Autodesk Fusion 360 part; units mm, degrees
(part 7 of 7)
component "rear deck crossmember" placed x (-1, 0, 0) y (0, 0, 1) z (0, 1, 0) at (-188, -315, 113)
component "front deck crossmember" placed x (-1, 0, 0) y (0, 0, 1) z (0, 1, 0) at (176, -315, 113)
component "left electronics deck" placed x (1, 0, 0) y (0, 1, 0) z (0, 0, 1) at (-5.5, 149, 122)
component "right electronics deck" placed x (1, 0, 0) y (0, 1, 0) z (0, 0, 1) at (-5.5, -147.5, 122)
component "fore electronics deck bridge" placed x (1, 0, 0) y (0, 1, 0) z (0, 0, 1) at (110.5, 1.5, 122)
component "aft electronics deck bridge" placed x (1, 0, 0) y (0, 1, 0) z (0, 0, 1) at (-157.5, 1.5, 122)
component "battery cradle floor" placed x (1, 0, 0) y (0, 1, 0) z (0, 0, 1) at (-41.5, 1.5, 44)
component "battery cradle wall -44" placed x (1, 0, 0) y (0, 1, 0) z (0, 0, 1) at (-41.5, -42, 48)
component "battery cradle wall 43" placed x (1, 0, 0) y (0, 1, 0) z (0, 0, 1) at (-41.5, 45, 48)
component "battery secured envelope" placed x (1, 0, 0) y (0, 1, 0) z (0, 0, 1) at (-41.5, 2, 48)
component "distribution enclosure reserve" placed x (1, 0, 0) y (0, 1, 0) z (0, 0, 1) at (105, -3, 129)
component "robot controller reserve" placed x (1, 0, 0) y (0, 1, 0) z (0, 0, 1) at (-79.5, 108, 129)
component "field radio reserve" placed x (1, 0, 0) y (0, 1, 0) z (0, 0, 1) at (-88.5, -118.5, 129)
component "drive controller reserve 1" placed x (1, 0, 0) y (0, 1, 0) z (0, 0, 1) at (-120.5, -204, 129)
component "drive controller reserve 2" placed x (1, 0, 0) y (0, 1, 0) z (0, 0, 1) at (-120.5, 204, 129)
component "drive controller reserve 3" placed x (1, 0, 0) y (0, 1, 0) z (0, 0, 1) at (-42.5, -204, 129)
component "drive controller reserve 4" placed x (1, 0, 0) y (0, 1, 0) z (0, 0, 1) at (-42.5, 204, 129)
component "drive controller reserve 5" placed x (1, 0, 0) y (0, 1, 0) z (0, 0, 1) at (35.5, -204, 129)
component "drive controller reserve 6" placed x (1, 0, 0) y (0, 1, 0) z (0, 0, 1) at (35.5, 204, 129)
component "drive controller reserve 7" placed x (1, 0, 0) y (0, 1, 0) z (0, 0, 1) at (113.5, -204, 129)
component "drive controller reserve 8" placed x (1, 0, 0) y (0, 1, 0) z (0, 0, 1) at (113.5, 204, 129)
component "hopper back panel" placed x (1, 0, 0) y (0, 1, 0) z (0, 0, 1) at (-332, 0, 232)
component "right hopper wall" placed x (1, 0, 0) y (0, 1, 0) z (0, 0, 1) at (-91, -313, 232)
component "right hopper front wing" placed x (1, 0, 0) y (0, 1, 0) z (0, 0, 1) at (150, -199, 232)
component "right cross feed deck" placed x (1, 0, 0) y (0, 1, 0) z (0, 0, 1) at (-91, -199, 230)
component "right front elevator upright" placed x (1, 0, 0) y (0, 1, 0) z (0, 0, 1) at (183, -105, 111)
component "right rear elevator upright" placed x (1, 0, 0) y (0, 1, 0) z (0, 0, 1) at (319, -105, 113)
component "right elevator upper tie" placed x (0, 1, 0) y (0, 0, 1) z (1, 0, 0) at (181, -105, 637)
component "right inside lift belt" placed x (1, 0, 0) y (0, 1, 0) z (0, 0, 1) at (196, -91, 86)
component "right outside lift belt" placed x (1, 0, 0) y (0, 1, 0) z (0, 0, 1) at (301, -91, 86)
component "right lift shelf 1" placed x (1, 0, 0) y (0, 1, 0) z (0, 0, 1) at (244, -81, 99)
component "right lift shelf 2" placed x (1, 0, 0) y (0, 1, 0) z (0, 0, 1) at (244, -81, 258)
component "right lift shelf 3" placed x (1, 0, 0) y (0, 1, 0) z (0, 0, 1) at (244, -81, 417)
component "right lift shelf 4" placed x (1, 0, 0) y (0, 1, 0) z (0, 0, 1) at (244, -81, 576)
component "right intake ramp" placed x (0, 1, 0) y (0.257178, 0, 0.966364) z (0.966364, 0, -0.257178) at (213, -60, 48)
component "left hopper wall" placed x (1, 0, 0) y (0, 1, 0) z (0, 0, 1) at (-91, 313, 232)
component "left hopper front wing" placed x (1, 0, 0) y (0, 1, 0) z (0, 0, 1) at (150, 199, 232)
component "left cross feed deck" placed x (1, 0, 0) y (0, 1, 0) z (0, 0, 1) at (-91, 199, 230)
component "left front elevator upright" placed x (1, 0, 0) y (0, 1, 0) z (0, 0, 1) at (183, 105, 111)
component "left rear elevator upright" placed x (1, 0, 0) y (0, 1, 0) z (0, 0, 1) at (319, 105, 113)
component "left elevator upper tie" placed x (0, 1, 0) y (0, 0, 1) z (1, 0, 0) at (181, 105, 637)
component "left inside lift belt" placed x (1, 0, 0) y (0, 1, 0) z (0, 0, 1) at (196, 91, 86)
component "left outside lift belt" placed x (1, 0, 0) y (0, 1, 0) z (0, 0, 1) at (301, 91, 86)
component "left lift shelf 1" placed x (1, 0, 0) y (0, 1, 0) z (0, 0, 1) at (244, 81, 99)
component "left lift shelf 2" placed x (1, 0, 0) y (0, 1, 0) z (0, 0, 1) at (244, 81, 258)
component "left lift shelf 3" placed x (1, 0, 0) y (0, 1, 0) z (0, 0, 1) at (244, 81, 417)
component "left lift shelf 4" placed x (1, 0, 0) y (0, 1, 0) z (0, 0, 1) at (244, 81, 576)
component "left intake ramp" placed x (0, 1, 0) y (0.257178, 0, 0.966364) z (0.966364, 0, -0.257178) at (213, 60, 48)
component "central fore-aft feed deck" placed x (1, 0, 0) y (0, 1, 0) z (0, 0, 1) at (-90.5, 0, 230)
component "left lower lift stub shaft" placed x (-1, 0, 0) y (0, 0, 1) z (0, 1, 0) at (248, 88, 84)
component "right lower lift stub shaft" placed x (-1, 0, 0) y (0, 0, 1) z (0, 1, 0) at (248, -116, 84)
component "left upper lift stub shaft" placed x (-1, 0, 0) y (0, 0, 1) z (0, 1, 0) at (248, 88, 622)
component "right upper lift stub shaft" placed x (-1, 0, 0) y (0, 0, 1) z (0, 1, 0) at (248, -116, 622)
component "ground intake roller" placed x (-1, 0, 0) y (0, 0, 1) z (0, 1, 0) at (285.7664, -126, 342.4358)
component "right intake bearing arm" placed x (0.994522, 0, -0.104528) y (0, 1, 0) z (0.104528, 0, 0.994522) at (275, -150, 240)
component "right intake pivot plate" placed x (0, -1, 0) y (-0.17238, 0, 0.98503) z (-0.98503, 0, -0.17238) at (315, -150, 247)
component "right intake pivot axle" placed x (-1, 0, 0) y (0, 0, 1) z (0, 1, 0) at (275, -150, 240)
component "right intake journal" placed x (-1, 0, 0) y (0, 0, 1) z (0, 1, 0) at (285.7664, -150, 342.4358)
component "right upper head cheek" placed x (1, 0, 0) y (0, 1, 0) z (0, 0, 1) at (236, -150, 562)
component "left intake bearing arm" placed x (0.994522, 0, -0.104528) y (0, 1, 0) z (0.104528, 0, 0.994522) at (275, 150, 240)
component "left intake pivot plate" placed x (0, -1, 0) y (-0.17238, 0, 0.98503) z (-0.98503, 0, -0.17238) at (315, 150, 247)
component "left intake pivot axle" placed x (-1, 0, 0) y (0, 0, 1) z (0, 1, 0) at (275, 100, 240)
component "left intake journal" placed x (-1, 0, 0) y (0, 0, 1) z (0, 1, 0) at (285.7664, 126, 342.4358)
component "left upper head cheek" placed x (1, 0, 0) y (0, 1, 0) z (0, 0, 1) at (236, 150, 562)
component "right scoring wheel" placed x (0, -1, 0) y (0.5, 0, 0.866025) z (-0.866025, 0, 0.5) at (259.6506, -104, 588.5)
component "right scoring spindle" placed x (0, -1, 0) y (0.5, 0, 0.866025) z (-0.866025, 0, 0.5) at (269.1769, -104, 583)
component "right upper guide" placed x (0, 1, 0) y (-0.841019, 0, 0.541006) z (0.541006, 0, 0.841019) at (190, -80, 548)
component "right scoring bearing bridge -33" placed x (-1, 0, 0) y (0, 0, 1) z (0, 1, 0) at (266.5788, -146, 584.5)
component "right scoring bearing bridge 33" placed x (-1, 0, 0) y (0, 0, 1) z (0, 1, 0) at (209.4212, -146, 617.5)
component "left scoring wheel" placed x (0, -1, 0) y (0.5, 0, 0.866025) z (-0.866025, 0, 0.5) at (259.6506, 104, 588.5)
component "left scoring spindle" placed x (0, -1, 0) y (0.5, 0, 0.866025) z (-0.866025, 0, 0.5) at (269.1769, 104, 583)
component "left upper guide" placed x (0, 1, 0) y (-0.841019, 0, 0.541006) z (0.541006, 0, 0.841019) at (190, 80, 548)
component "left scoring bearing bridge -33" placed x (-1, 0, 0) y (0, 0, 1) z (0, 1, 0) at (266.5788, 104, 584.5)
component "left scoring bearing bridge 33" placed x (-1, 0, 0) y (0, 0, 1) z (0, 1, 0) at (209.4212, 104, 617.5)
component "left feed diverter pivot" placed x (-1, 0, 0) y (0, 0, 1) z (0, 1, 0) at (156, 76, 548)
component "right feed diverter pivot" placed x (-1, 0, 0) y (0, 0, 1) z (0, 1, 0) at (156, -100, 548)
component "feed diverter vane" placed x (1, 0, 0) y (0, 1, 0) z (0, 0, 1) at (156, 0, 548)
component "front left public wheel" placed x (-1, 0, 0) y (0, 0, 1) z (0, 1, 0) at (268, 255, 38.1)
component "front left public drive housing" placed x (1, 0, 0) y (0, 1, 0) z (0, 0, 1) at (268, 268, 70)
component "front left public motor reserve" placed x (1, 0, 0) y (0, 1, 0) z (0, 0, 1) at (268, 268, 115)
component "front right public wheel" placed x (-1, 0, 0) y (0, 0, 1) z (0, 1, 0) at (268, -281, 38.1)
component "front right public drive housing" placed x (1, 0, 0) y (0, 1, 0) z (0, 0, 1) at (268, -268, 70)
component "front right public motor reserve" placed x (1, 0, 0) y (0, 1, 0) z (0, 0, 1) at (268, -268, 115)
component "rear left public wheel" placed x (-1, 0, 0) y (0, 0, 1) z (0, 1, 0) at (-268, 255, 38.1)
component "rear left public drive housing" placed x (1, 0, 0) y (0, 1, 0) z (0, 0, 1) at (-268, 268, 70)
component "rear left public motor reserve" placed x (1, 0, 0) y (0, 1, 0) z (0, 0, 1) at (-268, 268, 115)
component "rear right public wheel" placed x (-1, 0, 0) y (0, 0, 1) z (0, 1, 0) at (-268, -281, 38.1)
component "rear right public drive housing" placed x (1, 0, 0) y (0, 1, 0) z (0, 0, 1) at (-268, -268, 70)
component "rear right public motor reserve" placed x (1, 0, 0) y (0, 1, 0) z (0, 0, 1) at (-268, -268, 115)
component "right public scoring motor envelope" placed x (0, -1, 0) y (0.5, 0, 0.866025) z (-0.866025, 0, 0.5) at (213.7513, -104, 615)
component "left public scoring motor envelope" placed x (0, -1, 0) y (0.5, 0, 0.866025) z (-0.866025, 0, 0.5) at (213.7513, 104, 615)
component "rear lift custody gate" placed x (1, 0, 0) y (0, 1, 0) z (0, 0, 1) at (169, 0, 134)
component "front lift custody guide" placed x (1, 0, 0) y (0, 1, 0) z (0, 0, 1) at (329, 0, 221)
component "left mast" placed x (1, 0, 0) y (0, 1, 0) z (0, 0, 1) at (-180, 326, 114.8)
component "left aft mast" placed x (1, 0, 0) y (0, 1, 0) z (0, 0, 1) at (-280, 326, 114.8)
component "left upper bearing plate" placed x (1, 0, 0) y (0, 1, 0) z (0, 0, 1) at (-230, 317, 744)
component "left lower bearing plate" placed x (1, 0, 0) y (0, 1, 0) z (0, 0, 1) at (-240, 313.5, 551)
component "left lead screw envelope" placed x (1, 0, 0) y (0, 1, 0) z (0, 0, 1) at (-240, 305, 557)
component "left lift motor envelope" placed x (1, 0, 0) y (0, 1, 0) z (0, 0, 1) at (-240, 258, 577)
component "left reduction envelope" placed x (1, 0, 0) y (0, 1, 0) z (0, 0, 1) at (-240, 280, 557)
component "left driven nut" placed x (1, 0, 0) y (0, 1, 0) z (0, 0, 1) at (-240, 305.5, 711)
component "left nut link" placed x (1, 0, 0) y (0, 1, 0) z (0, 0, 1) at (-240, 306, 701)
component "left crosshead cheek" placed x (1, 0, 0) y (0, 1, 0) z (0, 0, 1) at (-204.5, 303.5, 687)
component "left forward carriage sleeve" placed x (1, 0, 0) y (0, 1, 0) z (0, 0, 1) at (-180, 326, 682)
component "left aft carriage sleeve" placed x (1, 0, 0) y (0, 1, 0) z (0, 0, 1) at (-280, 326, 682)
component "left extension sleeve" placed x (0, 1, 0) y (0, 0, 1) z (1, 0, 0) at (-173, 72, 739)
component "left sleeve pedestal" placed x (1, 0, 0) y (0, 1, 0) z (0, 0, 1) at (-153, 72, 701)
component "left extending rail" placed x (0, 1, 0) y (0, 0, 1) z (1, 0, 0) at (-220, 72, 739)
component "left crown hook" placed x (1, 0, 0) y (0, 0, 1) z (0, -1, 0) at (0, 94, 0)
component "right mast" placed x (1, 0, 0) y (0, 1, 0) z (0, 0, 1) at (-180, -326, 114.8)
component "right aft mast" placed x (1, 0, 0) y (0, 1, 0) z (0, 0, 1) at (-280, -326, 114.8)
component "right upper bearing plate" placed x (1, 0, 0) y (0, 1, 0) z (0, 0, 1) at (-230, -317, 744)
component "right lower bearing plate" placed x (1, 0, 0) y (0, 1, 0) z (0, 0, 1) at (-240, -313.5, 551)
component "right lead screw envelope" placed x (1, 0, 0) y (0, 1, 0) z (0, 0, 1) at (-240, -305, 557)
component "right lift motor envelope" placed x (1, 0, 0) y (0, 1, 0) z (0, 0, 1) at (-240, -258, 577)
component "right reduction envelope" placed x (1, 0, 0) y (0, 1, 0) z (0, 0, 1) at (-240, -280, 557)
component "right driven nut" placed x (1, 0, 0) y (0, 1, 0) z (0, 0, 1) at (-240, -305.5, 711)
component "right nut link" placed x (1, 0, 0) y (0, 1, 0) z (0, 0, 1) at (-240, -306, 701)
component "right crosshead cheek" placed x (1, 0, 0) y (0, 1, 0) z (0, 0, 1) at (-204.5, -303.5, 687)
component "right forward carriage sleeve" placed x (1, 0, 0) y (0, 1, 0) z (0, 0, 1) at (-180, -326, 682)
component "right aft carriage sleeve" placed x (1, 0, 0) y (0, 1, 0) z (0, 0, 1) at (-280, -326, 682)
component "right extension sleeve" placed x (0, 1, 0) y (0, 0, 1) z (1, 0, 0) at (-173, -72, 739)
component "right sleeve pedestal" placed x (1, 0, 0) y (0, 1, 0) z (0, 0, 1) at (-153, -72, 701)
component "right extending rail" placed x (0, 1, 0) y (0, 0, 1) z (1, 0, 0) at (-220, -72, 739)
component "right crown hook" placed x (1, 0, 0) y (0, 0, 1) z (0, -1, 0) at (0, -82, 0)
component "crosshead lift bridge" placed x (-1, 0, 0) y (0, 0, 1) z (0, 1, 0) at (-151, -315, 691)
component "rail synchronizing tie" placed x (1, 0, 0) y (0, 1, 0) z (0, 0, 1) at (163, 0, 750)
component "extension bearing beam" placed x (1, 0, 0) y (0, 1, 0) z (0, 0, 1) at (32, 0, 701)
component "extension rear bearing and stop" placed x (0, 1, 0) y (0, 0, 1) z (1, 0, 0) at (-74, 0, 733)
component "extension forward bearing" placed x (0, 1, 0) y (0, 0, 1) z (1, 0, 0) at (193, 0, 733)
component "extension screw envelope" placed x (0, 1, 0) y (0, 0, 1) z (1, 0, 0) at (-74, 0, 733)
component "extension deployment nut" placed x (0, 1, 0) y (0, 0, 1) z (1, 0, 0) at (153, 0, 733)
component "extension nut hanger" placed x (1, 0, 0) y (0, 1, 0) z (0, 0, 1) at (163, 0, 746)
component "extension motor envelope" placed x (0, 1, 0) y (0, 0, 1) z (1, 0, 0) at (205, 0, 733)
component "extension motor foot" placed x (1, 0, 0) y (0, 1, 0) z (0, 0, 1) at (215, 0, 716)
component "rear right crossmember backing plate" placed x (1, 0, 0) y (0, 1, 0) z (0, 0, 1) at (0, 0, 0)
component "rear left crossmember backing plate" placed x (1, 0, 0) y (0, 1, 0) z (0, 0, 1) at (0, 0, 0)
component "front right crossmember backing plate" placed x (1, 0, 0) y (0, 1, 0) z (0, 0, 1) at (0, 0, 0)
component "front left crossmember backing plate" placed x (1, 0, 0) y (0, 1, 0) z (0, 0, 1) at (0, 0, 0)
component "front left rail mount 1-1 weld boss" placed x (1, 0, 0) y (0, 1, 0) z (0, 0, 1) at (0, 0, 0)
component "front left rail mount 1-1 M6 cap screw" placed x (1, 0, 0) y (0, 1, 0) z (0, 0, 1) at (0, 0, 0)
component "front left rail mount 1-2 weld boss" placed x (1, 0, 0) y (0, 1, 0) z (0, 0, 1) at (0, 0, 0)
component "front left rail mount 1-2 M6 cap screw" placed x (1, 0, 0) y (0, 1, 0) z (0, 0, 1) at (0, 0, 0)
component "front left tab 1-1 socket screw" placed x (1, 0, 0) y (0, 1, 0) z (0, 0, 1) at (0, 0, 0)
component "front left tab 1-1 locknut" placed x (1, 0, 0) y (0, 1, 0) z (0, 0, 1) at (0, 0, 0)
component "front left tab 1-2 socket screw" placed x (1, 0, 0) y (0, 1, 0) z (0, 0, 1) at (0, 0, 0)
component "front left tab 1-2 locknut" placed x (1, 0, 0) y (0, 1, 0) z (0, 0, 1) at (0, 0, 0)
component "front left rail mount 2-1 weld boss" placed x (1, 0, 0) y (0, 1, 0) z (0, 0, 1) at (0, 0, 0)
component "front left rail mount 2-1 M6 cap screw" placed x (1, 0, 0) y (0, 1, 0) z (0, 0, 1) at (0, 0, 0)
component "front left rail mount 2-2 weld boss" placed x (1, 0, 0) y (0, 1, 0) z (0, 0, 1) at (0, 0, 0)
component "front left rail mount 2-2 M6 cap screw" placed x (1, 0, 0) y (0, 1, 0) z (0, 0, 1) at (0, 0, 0)
component "front left tab 2-1 socket screw" placed x (1, 0, 0) y (0, 1, 0) z (0, 0, 1) at (0, 0, 0)
component "front left tab 2-1 locknut" placed x (1, 0, 0) y (0, 1, 0) z (0, 0, 1) at (0, 0, 0)
component "front left tab 2-2 socket screw" placed x (1, 0, 0) y (0, 1, 0) z (0, 0, 1) at (0, 0, 0)
component "front left tab 2-2 locknut" placed x (1, 0, 0) y (0, 1, 0) z (0, 0, 1) at (0, 0, 0)
component "front right rail mount 1-1 weld boss" placed x (1, 0, 0) y (0, 1, 0) z (0, 0, 1) at (0, 0, 0)
component "front right rail mount 1-1 M6 cap screw" placed x (1, 0, 0) y (0, 1, 0) z (0, 0, 1) at (0, 0, 0)
component "front right rail mount 1-2 weld boss" placed x (1, 0, 0) y (0, 1, 0) z (0, 0, 1) at (0, 0, 0)
component "front right rail mount 1-2 M6 cap screw" placed x (1, 0, 0) y (0, 1, 0) z (0, 0, 1) at (0, 0, 0)
component "front right tab 1-1 socket screw" placed x (1, 0, 0) y (0, 1, 0) z (0, 0, 1) at (0, 0, 0)
component "front right tab 1-1 locknut" placed x (1, 0, 0) y (0, 1, 0) z (0, 0, 1) at (0, 0, 0)
component "front right tab 1-2 socket screw" placed x (1, 0, 0) y (0, 1, 0) z (0, 0, 1) at (0, 0, 0)
component "front right tab 1-2 locknut" placed x (1, 0, 0) y (0, 1, 0) z (0, 0, 1) at (0, 0, 0)
component "front right rail mount 2-1 weld boss" placed x (1, 0, 0) y (0, 1, 0) z (0, 0, 1) at (0, 0, 0)
component "front right rail mount 2-1 M6 cap screw" placed x (1, 0, 0) y (0, 1, 0) z (0, 0, 1) at (0, 0, 0)
component "front right rail mount 2-2 weld boss" placed x (1, 0, 0) y (0, 1, 0) z (0, 0, 1) at (0, 0, 0)
component "front right rail mount 2-2 M6 cap screw" placed x (1, 0, 0) y (0, 1, 0) z (0, 0, 1) at (0, 0, 0)
component "front right tab 2-1 socket screw" placed x (1, 0, 0) y (0, 1, 0) z (0, 0, 1) at (0, 0, 0)
component "front right tab 2-1 locknut" placed x (1, 0, 0) y (0, 1, 0) z (0, 0, 1) at (0, 0, 0)
component "front right tab 2-2 socket screw" placed x (1, 0, 0) y (0, 1, 0) z (0, 0, 1) at (0, 0, 0)
component "front right tab 2-2 locknut" placed x (1, 0, 0) y (0, 1, 0) z (0, 0, 1) at (0, 0, 0)
component "rear left rail mount 1-1 weld boss" placed x (1, 0, 0) y (0, 1, 0) z (0, 0, 1) at (0, 0, 0)
component "rear left rail mount 1-1 M6 cap screw" placed x (1, 0, 0) y (0, 1, 0) z (0, 0, 1) at (0, 0, 0)
component "rear left rail mount 1-2 weld boss" placed x (1, 0, 0) y (0, 1, 0) z (0, 0, 1) at (0, 0, 0)
component "rear left rail mount 1-2 M6 cap screw" placed x (1, 0, 0) y (0, 1, 0) z (0, 0, 1) at (0, 0, 0)
component "rear left tab 1-1 socket screw" placed x (1, 0, 0) y (0, 1, 0) z (0, 0, 1) at (0, 0, 0)
component "rear left tab 1-1 locknut" placed x (1, 0, 0) y (0, 1, 0) z (0, 0, 1) at (0, 0, 0)
component "rear left tab 1-2 socket screw" placed x (1, 0, 0) y (0, 1, 0) z (0, 0, 1) at (0, 0, 0)
component "rear left tab 1-2 locknut" placed x (1, 0, 0) y (0, 1, 0) z (0, 0, 1) at (0, 0, 0)
component "rear left rail mount 2-1 weld boss" placed x (1, 0, 0) y (0, 1, 0) z (0, 0, 1) at (0, 0, 0)
component "rear left rail mount 2-1 M6 cap screw" placed x (1, 0, 0) y (0, 1, 0) z (0, 0, 1) at (0, 0, 0)
component "rear left rail mount 2-2 weld boss" placed x (1, 0, 0) y (0, 1, 0) z (0, 0, 1) at (0, 0, 0)
component "rear left rail mount 2-2 M6 cap screw" placed x (1, 0, 0) y (0, 1, 0) z (0, 0, 1) at (0, 0, 0)
component "rear left tab 2-1 socket screw" placed x (1, 0, 0) y (0, 1, 0) z (0, 0, 1) at (0, 0, 0)
component "rear left tab 2-1 locknut" placed x (1, 0, 0) y (0, 1, 0) z (0, 0, 1) at (0, 0, 0)
component "rear left tab 2-2 socket screw" placed x (1, 0, 0) y (0, 1, 0) z (0, 0, 1) at (0, 0, 0)
component "rear left tab 2-2 locknut" placed x (1, 0, 0) y (0, 1, 0) z (0, 0, 1) at (0, 0, 0)
component "rear right rail mount 1-1 weld boss" placed x (1, 0, 0) y (0, 1, 0) z (0, 0, 1) at (0, 0, 0)
component "rear right rail mount 1-1 M6 cap screw" placed x (1, 0, 0) y (0, 1, 0) z (0, 0, 1) at (0, 0, 0)
component "rear right rail mount 1-2 weld boss" placed x (1, 0, 0) y (0, 1, 0) z (0, 0, 1) at (0, 0, 0)
component "rear right rail mount 1-2 M6 cap screw" placed x (1, 0, 0) y (0, 1, 0) z (0, 0, 1) at (0, 0, 0)
component "rear right tab 1-1 socket screw" placed x (1, 0, 0) y (0, 1, 0) z (0, 0, 1) at (0, 0, 0)
component "rear right tab 1-1 locknut" placed x (1, 0, 0) y (0, 1, 0) z (0, 0, 1) at (0, 0, 0)
component "rear right tab 1-2 socket screw" placed x (1, 0, 0) y (0, 1, 0) z (0, 0, 1) at (0, 0, 0)
component "rear right tab 1-2 locknut" placed x (1, 0, 0) y (0, 1, 0) z (0, 0, 1) at (0, 0, 0)
component "rear right rail mount 2-1 weld boss" placed x (1, 0, 0) y (0, 1, 0) z (0, 0, 1) at (0, 0, 0)
component "rear right rail mount 2-1 M6 cap screw" placed x (1, 0, 0) y (0, 1, 0) z (0, 0, 1) at (0, 0, 0)
component "rear right rail mount 2-2 weld boss" placed x (1, 0, 0) y (0, 1, 0) z (0, 0, 1) at (0, 0, 0)
component "rear right rail mount 2-2 M6 cap screw" placed x (1, 0, 0) y (0, 1, 0) z (0, 0, 1) at (0, 0, 0)
component "rear right tab 2-1 socket screw" placed x (1, 0, 0) y (0, 1, 0) z (0, 0, 1) at (0, 0, 0)
component "rear right tab 2-1 locknut" placed x (1, 0, 0) y (0, 1, 0) z (0, 0, 1) at (0, 0, 0)
component "rear right tab 2-2 socket screw" placed x (1, 0, 0) y (0, 1, 0) z (0, 0, 1) at (0, 0, 0)
component "rear right tab 2-2 locknut" placed x (1, 0, 0) y (0, 1, 0) z (0, 0, 1) at (0, 0, 0)
component "front left public turning fork" placed x (1, 0, 0) y (0, 1, 0) z (0, 0, 1) at (0, 0, 0)
component "front left public wheel axle" placed x (1, 0, 0) y (0, 1, 0) z (0, 0, 1) at (0, 0, 0)
component "front right public turning fork" placed x (1, 0, 0) y (0, 1, 0) z (0, 0, 1) at (0, 0, 0)
component "front right public wheel axle" placed x (1, 0, 0) y (0, 1, 0) z (0, 0, 1) at (0, 0, 0)
component "rear left public turning fork" placed x (1, 0, 0) y (0, 1, 0) z (0, 0, 1) at (0, 0, 0)
component "rear left public wheel axle" placed x (1, 0, 0) y (0, 1, 0) z (0, 0, 1) at (0, 0, 0)
component "rear right public turning fork" placed x (1, 0, 0) y (0, 1, 0) z (0, 0, 1) at (0, 0, 0)
component "rear right public wheel axle" placed x (1, 0, 0) y (0, 1, 0) z (0, 0, 1) at (0, 0, 0)
component "left white 1780 digit 1" placed x (1, 0, 0) y (0, 1, 0) z (0, 0, 1) at (0, 0, 0)
component "left white 1780 digit 7" placed x (1, 0, 0) y (0, 1, 0) z (0, 0, 1) at (0, 0, 0)
component "left white 1780 digit 8" placed x (1, 0, 0) y (0, 1, 0) z (0, 0, 1) at (0, 0, 0)
component "left white 1780 digit 0" placed x (1, 0, 0) y (0, 1, 0) z (0, 0, 1) at (0, 0, 0)
component "right white 1780 digit 1" placed x (1, 0, 0) y (0, 1, 0) z (0, 0, 1) at (0, 0, 0)
component "right white 1780 digit 7" placed x (1, 0, 0) y (0, 1, 0) z (0, 0, 1) at (0, 0, 0)
component "right white 1780 digit 8" placed x (1, 0, 0) y (0, 1, 0) z (0, 0, 1) at (0, 0, 0)
component "right white 1780 digit 0" placed x (1, 0, 0) y (0, 1, 0) z (0, 0, 1) at (0, 0, 0)
component "rear white 1780 digit 1" placed x (1, 0, 0) y (0, 1, 0) z (0, 0, 1) at (0, 0, 0)
component "rear white 1780 digit 7" placed x (1, 0, 0) y (0, 1, 0) z (0, 0, 1) at (0, 0, 0)
component "rear white 1780 digit 8" placed x (1, 0, 0) y (0, 1, 0) z (0, 0, 1) at (0, 0, 0)
component "rear white 1780 digit 0" placed x (1, 0, 0) y (0, 1, 0) z (0, 0, 1) at (0, 0, 0)
component "front white 1780 digit 1" placed x (1, 0, 0) y (0, 1, 0) z (0, 0, 1) at (0, 0, 0)
component "front white 1780 digit 7" placed x (1, 0, 0) y (0, 1, 0) z (0, 0, 1) at (0, 0, 0)
component "front white 1780 digit 8" placed x (1, 0, 0) y (0, 1, 0) z (0, 0, 1) at (0, 0, 0)
component "front white 1780 digit 0" placed x (1, 0, 0) y (0, 1, 0) z (0, 0, 1) at (0, 0, 0)
component "left intake foundation cheek" placed x (1, 0, 0) y (0, 1, 0) z (0, 0, 1) at (0, 0, 0)
component "left ramp bridge aft" placed x (1, 0, 0) y (0, 1, 0) z (0, 0, 1) at (0, 0, 0)
component "left ramp bridge forward" placed x (1, 0, 0) y (0, 1, 0) z (0, 0, 1) at (0, 0, 0)
component "right intake foundation cheek" placed x (1, 0, 0) y (0, 1, 0) z (0, 0, 1) at (0, 0, 0)
component "right ramp bridge aft" placed x (1, 0, 0) y (0, 1, 0) z (0, 0, 1) at (0, 0, 0)
component "right ramp bridge forward" placed x (1, 0, 0) y (0, 1, 0) z (0, 0, 1) at (0, 0, 0)
component "right red side bumper" placed x (1, 0, 0) y (0, 1, 0) z (0, 0, 1) at (0, -378, 48) in component "rail synchronizing tie"
component "front right module tab spacer 1" placed x (1, 0, 0) y (0, 1, 0) z (0, 0, 1) at (303.05, -198, 78.32) in component "rear right tab 1-1 socket screw"
equation "d1905 = -( 4.50 mm )"
equation "d1909 = -( 4.50 mm )"
equation "d1913 = -( 4.50 mm )"
equation "d1917 = -( 4.50 mm )"
equation "d1949 = -( 4.50 mm )"
equation "d1953 = -( 4.50 mm )"
equation "d1957 = -( 4.50 mm )"
equation "d1961 = -( 4.50 mm )"
equation "d1977 = -( 44.00 mm )"
equation "d1981 = -( 44.00 mm )"
equation "d2009 = -( 0.12 mm )"
equation "d2013 = -( 0.12 mm )"
equation "d2017 = -( 0.12 mm )"
equation "d2021 = -( 0.12 mm )"
equation "d2025 = -( 0.12 mm )"
equation "d2029 = -( 0.12 mm )"
equation "d2033 = -( 0.12 mm )"
equation "d2037 = -( 0.12 mm )"
equation "d2069 = -( 6.00 mm )"
named bodies: "left red side bumper", "left red front bumper", "right red side bumper", "right red front bumper", "rear red bumper", "left electronics deck", "right electronics deck", "fore electronics deck bridge", "aft electronics deck bridge", "battery cradle floor", "battery cradle wall -44", "battery cradle wall 43", "battery secured envelope", "distribution enclosure reserve", "robot controller reserve", "field radio reserve", "drive controller reserve 1", "drive controller reserve 2", "drive controller reserve 3", "drive controller reserve 4", "drive controller reserve 5", "drive controller reserve 6", "drive controller reserve 7", "drive controller reserve 8", "hopper back panel", "right hopper wall", "right hopper front wing", "right cross feed deck", "right front elevator upright", "right rear elevator upright", "right elevator upper tie", "right inside lift belt", "right outside lift belt", "right lift shelf 1", "right lift shelf 2", "right lift shelf 3", "right lift shelf 4", "right intake ramp", "left hopper wall", "left hopper front wing", "left cross feed deck", "left front elevator upright", "left rear elevator upright", "left elevator upper tie", "left inside lift belt", "left outside lift belt", "left lift shelf 1", "left lift shelf 2", "left lift shelf 3", "left lift shelf 4", "left intake ramp", "central fore-aft feed deck", "left lower lift stub shaft", "right lower lift stub shaft", "left upper lift stub shaft", "right upper lift stub shaft", "ground intake roller", "right intake bearing arm", "right intake pivot plate", "right intake pivot axle", "right intake journal", "right upper head cheek", "left intake bearing arm", "left intake pivot plate", "left intake pivot axle", "left intake journal", "left upper head cheek", "right scoring wheel", "right scoring spindle", "right upper guide", "right scoring bearing bridge -33", "right scoring bearing bridge 33", "left scoring wheel", "left scoring spindle", "left upper guide", "left scoring bearing bridge -33", "left scoring bearing bridge 33", "left feed diverter pivot", "right feed diverter pivot", "feed diverter vane", "right public scoring motor envelope", "left public scoring motor envelope", "rear lift custody gate", "front lift custody guide", "left mast", "left aft mast", "left upper bearing plate", "left lower bearing plate", "left lead screw envelope", "left lift motor envelope", "left reduction envelope", "left driven nut", "left nut link", "left crosshead cheek", "left forward carriage sleeve", "left aft carriage sleeve", "left extension sleeve", "left sleeve pedestal", "left extending rail", "left crown hook", "right mast", "right aft mast", "right upper bearing plate", "right lower bearing plate", "right lead screw envelope", "right lift motor envelope", "right reduction envelope", "right driven nut", "right nut link", "right crosshead cheek", "right forward carriage sleeve", "right aft carriage sleeve", "right extension sleeve", "right sleeve pedestal", "right extending rail", "right crown hook", "crosshead lift bridge", "rail synchronizing tie", "extension bearing beam", "extension rear bearing and stop", "extension forward bearing", "extension screw envelope", "extension deployment nut", "extension nut hanger", "extension motor envelope", "extension motor foot", "rear perimeter tube", "right perimeter tube", "right front return", "right floor sill", "rear right hopper post", "front right hopper post", "left perimeter tube", "left front return", "left floor sill", "rear left hopper post", "front left hopper post", "rear deck crossmember", "rear right crossmember backing plate", "rear left crossmember backing plate", "front deck crossmember", "front right crossmember backing plate", "front left crossmember backing plate", "front left module tab spacer 1", "front left module tab spacer 2", "front right module tab spacer 1", "front right module tab spacer 2", "rear left module tab spacer 1", "rear left module tab spacer 2", "rear right module tab spacer 1", "rear right module tab spacer 2", "front left rail mount 1-1 weld boss", "front left rail mount 1-1 M6 cap screw", "front left rail mount 1-2 weld boss", "front left rail mount 1-2 M6 cap screw", "front left tab 1-1 socket screw", "front left tab 1-1 locknut", "front left tab 1-2 socket screw", "front left tab 1-2 locknut", "front left rail mount 2-1 weld boss", "front left rail mount 2-1 M6 cap screw", "front left rail mount 2-2 weld boss", "front left rail mount 2-2 M6 cap screw", "front left tab 2-1 socket screw", "front left tab 2-1 locknut", "front left tab 2-2 socket screw", "front left tab 2-2 locknut", "front right rail mount 1-1 weld boss", "front right rail mount 1-1 M6 cap screw", "front right rail mount 1-2 weld boss", "front right rail mount 1-2 M6 cap screw", "front right tab 1-1 socket screw", "front right tab 1-1 locknut", "front right tab 1-2 socket screw", "front right tab 1-2 locknut", "front right rail mount 2-1 weld boss", "front right rail mount 2-1 M6 cap screw", "front right rail mount 2-2 weld boss", "front right rail mount 2-2 M6 cap screw", "front right tab 2-1 socket screw", "front right tab 2-1 locknut", "front right tab 2-2 socket screw", "front right tab 2-2 locknut", "rear left rail mount 1-1 weld boss", "rear left rail mount 1-1 M6 cap screw", "rear left rail mount 1-2 weld boss", "rear left rail mount 1-2 M6 cap screw", "rear left tab 1-1 socket screw", "rear left tab 1-1 locknut", "rear left tab 1-2 socket screw", "rear left tab 1-2 locknut", "rear left rail mount 2-1 weld boss", "rear left rail mount 2-1 M6 cap screw", "rear left rail mount 2-2 weld boss", "rear left rail mount 2-2 M6 cap screw", "rear left tab 2-1 socket screw", "rear left tab 2-1 locknut", "rear left tab 2-2 socket screw", "rear left tab 2-2 locknut", "rear right rail mount 1-1 weld boss", "rear right rail mount 1-1 M6 cap screw", "rear right rail mount 1-2 weld boss", "rear right rail mount 1-2 M6 cap screw", "rear right tab 1-1 socket screw", "rear right tab 1-1 locknut", "rear right tab 1-2 socket screw", "rear right tab 1-2 locknut", "rear right rail mount 2-1 weld boss", "rear right rail mount 2-1 M6 cap screw", "rear right rail mount 2-2 weld boss", "rear right rail mount 2-2 M6 cap screw", "rear right tab 2-1 socket screw", "rear right tab 2-1 locknut", "rear right tab 2-2 socket screw", "rear right tab 2-2 locknut", "front left public drive housing", "front left public motor reserve", "front left public turning fork", "front left public wheel axle", "front left public wheel", "front right public drive housing", "front right public motor reserve", "front right public turning fork", "front right public wheel axle", "front right public wheel", "rear left public drive housing", "rear left public motor reserve", "rear left public turning fork", "rear left public wheel axle", "rear left public wheel", "rear right public drive housing", "rear right public motor reserve", "rear right public turning fork", "rear right public wheel axle", "rear right public wheel", "left white 1780 digit 1", "left white 1780 digit 7", "left white 1780 digit 8", "left white 1780 digit 0", "right white 1780 digit 1", "right white 1780 digit 7", "right white 1780 digit 8", "right white 1780 digit 0", "rear white 1780 digit 1", "rear white 1780 digit 7", "rear white 1780 digit 8", "rear white 1780 digit 0", "front white 1780 digit 1", "front white 1780 digit 7", "front white 1780 digit 8", "front white 1780 digit 0", "left intake foundation cheek", "left ramp bridge aft", "left ramp bridge forward", "right intake foundation cheek", "right ramp bridge aft", "right ramp bridge forward"
